Autodesk Fusion 360 part; units mm, degrees
(part 4 of 4)
  spline S141 degree 3 poles (-72.7265, -168.4304) (-72.7884, -168.2804) (-72.9148, -167.9746) (-72.9308, -167.6439) (-72.9389, -167.4754) knots 0 0 0 0 0.048305 0.098484 0.098484 0.098484 0.098484
  spline S142 degree 3 poles (-72.9389, -167.4754) (-72.9169, -167.1911) (-72.8736, -166.6318) (-72.5364, -166.1842) (-72.3707, -165.9642) knots 0 0 0 0 0.083642 0.164485 0.164485 0.164485 0.164485
  spline S143 degree 3 poles (-72.3707, -165.9642) (-72.1132, -165.7849) (-71.5025, -165.3598) (-70.7517, -165.351) (-70.3175, -165.3458) knots 0 0 0 0 0.092246 0.218774 0.218774 0.218774 0.218774
  line L141 (-70.3175, -165.3458) -> (-68.5222, -165.3458)
  spline S144 degree 3 poles (-60.5385, -163.7916) (-60.4695, -163.7159) (-60.3365, -163.5701) (-60.2279, -163.4053) (-60.1756, -163.3261) knots 0 0 0 0 0.03068 0.059109 0.059109 0.059109 0.059109
  line L142 (-60.1756, -163.3261) -> (-63.6088, -163.3261)
  line L143 (-63.6088, -163.3261) -> (-63.6088, -162.5)
  line L144 (-63.6088, -162.5) -> (-58.9819, -162.5)
  spline S145 degree 3 poles (-58.9819, -162.5) (-58.9837, -162.6023) (-58.9871, -162.8063) (-59.0506, -163.0002) (-59.0822, -163.0969) knots 0 0 0 0 0.030508 0.060828 0.060828 0.060828 0.060828
  spline S146 degree 3 poles (-59.0822, -163.0969) (-59.1526, -163.257) (-59.3001, -163.5921) (-59.5286, -163.8784) (-59.648, -164.028) knots 0 0 0 0 0.052239 0.109365 0.109365 0.109365 0.109365
  spline S147 degree 3 poles (-59.648, -164.028) (-59.8035, -164.1959) (-60.1542, -164.5746) (-60.5514, -164.9044) (-60.7725, -165.088) knots 0 0 0 0 0.068595 0.154681 0.154681 0.154681 0.154681
  spline S148 degree 3 poles (-60.7725, -165.088) (-61.1011, -165.3574) (-61.6548, -165.8114) (-62.1241, -166.3512) (-62.3148, -166.5706) knots 0 0 0 0 0.127181 0.214261 0.214261 0.214261 0.214261
  spline S149 degree 3 poles (-62.3148, -166.5706) (-62.4315, -166.7418) (-62.646, -167.0563) (-62.694, -167.4328) (-62.7159, -167.6044) knots 0 0 0 0 0.061099 0.112287 0.112287 0.112287 0.112287
  spline S150 degree 3 poles (-62.7159, -167.6044) (-62.7008, -167.7679) (-62.6707, -168.0941) (-62.4572, -168.3424) (-62.3506, -168.4662) knots 0 0 0 0 0.04797 0.095708 0.095708 0.095708 0.095708
  spline S151 degree 3 poles (-62.3506, -168.4662) (-62.2159, -168.5685) (-61.9348, -168.782) (-61.5818, -168.8051) (-61.398, -168.8172) knots 0 0 0 0 0.049633 0.103533 0.103533 0.103533 0.103533
  spline S152 degree 3 poles (-61.398, -168.8172) (-61.2046, -168.8047) (-60.8349, -168.7809) (-60.5437, -168.5533) (-60.4048, -168.4447) knots 0 0 0 0 0.056637 0.108292 0.108292 0.108292 0.108292
  spline S153 degree 3 poles (-60.4048, -168.4447) (-60.2961, -168.3025) (-60.0641, -167.9991) (-60.0403, -167.6166) (-60.0276, -167.4134) knots 0 0 0 0 0.052525 0.112047 0.112047 0.112047 0.112047
  line L145 (-60.0276, -167.4134) -> (-59.1443, -167.5041)
  spline S154 degree 3 poles (-59.1443, -167.5041) (-59.1884, -167.8075) (-59.2712, -168.3775) (-59.6499, -168.8088) (-59.8271, -169.0106) knots 0 0 0 0 0.089723 0.168584 0.168584 0.168584 0.168584
  spline S155 degree 3 poles (-59.8271, -169.0106) (-60.051, -169.1615) (-60.53, -169.4844) (-61.1089, -169.5133) (-61.4171, -169.5286) knots 0 0 0 0 0.079498 0.170078 0.170078 0.170078 0.170078
  spline S156 degree 3 poles (-61.4171, -169.5286) (-61.7286, -169.5115) (-62.3162, -169.4792) (-62.7896, -169.1328) (-63.0119, -168.97) knots 0 0 0 0 0.09132 0.172247 0.172247 0.172247 0.172247
  spline S157 degree 3 poles (-63.0119, -168.97) (-63.1832, -168.7719) (-63.5277, -168.3736) (-63.5753, -167.849) (-63.5993, -167.5853) knots 0 0 0 0 0.076505 0.153832 0.153832 0.153832 0.153832
  spline S158 degree 3 poles (-63.5993, -167.5853) (-63.5917, -167.445) (-63.5765, -167.1609) (-63.4775, -166.8942) (-63.4274, -166.7592) knots 0 0 0 0 0.041882 0.084809 0.084809 0.084809 0.084809
  spline S159 degree 3 poles (-63.4274, -166.7592) (-63.3561, -166.6171) (-63.2014, -166.3088) (-62.9775, -166.0461) (-62.8567, -165.9045) knots 0 0 0 0 0.04752 0.103099 0.103099 0.103099 0.103099
  spline S160 degree 3 poles (-62.8567, -165.9045) (-62.6822, -165.7246) (-62.2618, -165.2912) (-61.8011, -164.9009) (-61.5317, -164.6726) knots 0 0 0 0 0.075166 0.181017 0.181017 0.181017 0.181017
  spline S161 degree 3 poles (-61.5317, -164.6726) (-61.3174, -164.4938) (-60.9774, -164.2102) (-60.657, -163.9046) (-60.5385, -163.7916) knots 0 0 0 0 0.083681 0.13279 0.13279 0.13279 0.13279
  spline S162 degree 3 poles (-51.1801, -13.3847) (-51.3211, -13.3941) (-51.5954, -13.4125) (-51.8227, -13.5664) (-51.9332, -13.6412) knots 0 0 0 0 0.041561 0.080838 0.080838 0.080838 0.080838
  spline S163 degree 3 poles (-51.9332, -13.6412) (-52.0286, -13.7421) (-52.2336, -13.9588) (-52.3099, -14.248) (-52.3506, -14.4025) knots 0 0 0 0 0.041026 0.088063 0.088063 0.088063 0.088063
  line L146 (-52.3506, -14.4025) -> (-52.8799, -14.2688)
  spline S164 degree 3 poles (-52.8799, -14.2688) (-52.8176, -14.0678) (-52.6993, -13.6863) (-52.4154, -13.4066) (-52.281, -13.2742) knots 0 0 0 0 0.062011 0.117707 0.117707 0.117707 0.117707
  spline S165 degree 3 poles (-52.281, -13.2742) (-52.1256, -13.1744) (-51.8037, -12.9677) (-51.4214, -12.944) (-51.2237, -12.9318) knots 0 0 0 0 0.054488 0.112794 0.112794 0.112794 0.112794
  spline S166 degree 3 poles (-51.2237, -12.9318) (-51.0244, -12.939) (-50.6543, -12.9523) (-50.3242, -13.1184) (-50.1719, -13.1951) knots 0 0 0 0 0.058997 0.109568 0.109568 0.109568 0.109568
  spline S167 degree 3 poles (-50.1719, -13.1951) (-50.0439, -13.2951) (-49.7798, -13.5015) (-49.6316, -13.8026) (-49.5553, -13.9577) knots 0 0 0 0 0.048078 0.099208 0.099208 0.099208 0.099208
  spline S168 degree 3 poles (-49.5553, -13.9577) (-49.4936, -14.1285) (-49.3685, -14.4751) (-49.3521, -14.8433) (-49.3438, -15.03) knots 0 0 0 0 0.054148 0.109857 0.109857 0.109857 0.109857
  spline S169 degree 3 poles (-49.3438, -15.03) (-49.3518, -15.2277) (-49.367, -15.6055) (-49.5129, -15.9539) (-49.5825, -16.1201) knots 0 0 0 0 0.058796 0.112388 0.112388 0.112388 0.112388
  spline S170 degree 3 poles (-49.5825, -16.1201) (-49.6697, -16.2654) (-49.8423, -16.5529) (-50.1231, -16.7361) (-50.2619, -16.8267) knots 0 0 0 0 0.050116 0.099176 0.099176 0.099176 0.099176
  spline S171 degree 3 poles (-50.2619, -16.8267) (-50.4137, -16.8972) (-50.7214, -17.04) (-51.0602, -17.0587) (-51.2319, -17.0682) knots 0 0 0 0 0.049699 0.100774 0.100774 0.100774 0.100774
  spline S172 degree 3 poles (-51.2319, -17.0682) (-51.4208, -17.0578) (-51.7828, -17.038) (-52.0931, -16.8517) (-52.2415, -16.7626) knots 0 0 0 0 0.055778 0.106905 0.106905 0.106905 0.106905
  spline S173 degree 3 poles (-52.2415, -16.7626) (-52.3684, -16.6475) (-52.6307, -16.4096) (-52.7501, -16.0756) (-52.8117, -15.9031) knots 0 0 0 0 0.05057 0.104573 0.104573 0.104573 0.104573
  line L147 (-52.8117, -15.9031) -> (-52.2906, -15.7804)
  spline S174 degree 3 poles (-52.2906, -15.7804) (-52.2434, -15.9124) (-52.1566, -16.1556) (-51.9714, -16.3344) (-51.8868, -16.4161) knots 0 0 0 0 0.041397 0.07622 0.07622 0.07622 0.07622
  spline S175 degree 3 poles (-51.8868, -16.4161) (-51.7897, -16.4742) (-51.5851, -16.5966) (-51.3465, -16.6088) (-51.221, -16.6153) knots 0 0 0 0 0.033404 0.070439 0.070439 0.070439 0.070439
  spline S176 degree 3 poles (-51.221, -16.6153) (-51.0766, -16.6081) (-50.8019, -16.5945) (-50.5633, -16.4587) (-50.4502, -16.3943) knots 0 0 0 0 0.042685 0.08119 0.08119 0.08119 0.08119
  spline S177 degree 3 poles (-50.4502, -16.3943) (-50.3545, -16.3138) (-50.1613, -16.1513) (-50.0641, -15.9183) (-50.015, -15.8008) knots 0 0 0 0 0.036948 0.074549 0.074549 0.074549 0.074549
  spline S178 degree 3 poles (-50.015, -15.8008) (-49.9784, -15.6756) (-49.9051, -15.4247) (-49.8947, -15.1635) (-49.8895, -15.0327) knots 0 0 0 0 0.038978 0.078087 0.078087 0.078087 0.078087
  spline S179 degree 3 poles (-49.8895, -15.0327) (-49.8942, -14.8721) (-49.903, -14.5682) (-49.9949, -14.2785) (-50.0382, -14.1419) knots 0 0 0 0 0.047928 0.09071 0.09071 0.09071 0.09071
  spline S180 degree 3 poles (-50.0382, -14.1419) (-50.093, -14.024) (-50.1994, -13.7952) (-50.4023, -13.6456) (-50.5007, -13.573) knots 0 0 0 0 0.038298 0.074371 0.074371 0.074371 0.074371
  spline S181 degree 3 poles (-50.5007, -13.573) (-50.6074, -13.5181) (-50.8209, -13.4083) (-51.0604, -13.3926) (-51.1801, -13.3847) knots 0 0 0 0 0.035595 0.071173 0.071173 0.071173 0.071173
  line L148 (-58.3806, -16.1432) -> (-58.3806, -13)
  line L149 (-58.3806, -13) -> (-57.8731, -13)
  line L150 (-57.8731, -13) -> (-57.8731, -17)
  line L151 (-57.8731, -17) -> (-58.4161, -17)
  line L152 (-58.4161, -17) -> (-60.5171, -13.8595)
  line L153 (-60.5171, -13.8595) -> (-60.5171, -17)
  line L154 (-60.5171, -17) -> (-61.0246, -17)
  line L155 (-61.0246, -17) -> (-61.0246, -13)
  line L156 (-61.0246, -13) -> (-60.4816, -13)
  line L157 (-60.4816, -13) -> (-58.3806, -16.1432)
  line L158 (-65.8649, -14.7763) -> (-65.8649, -13)
  line L159 (-65.8649, -13) -> (-65.3356, -13)
  line L160 (-65.3356, -13) -> (-65.3356, -17)
  line L161 (-65.3356, -17) -> (-67.1091, -17)
  spline S182 degree 3 poles (-67.1091, -17) (-67.2672, -16.9988) (-67.5431, -16.9967) (-67.8087, -16.9235) (-67.9222, -16.8922) knots 0 0 0 0 0.047144 0.082328 0.082328 0.082328 0.082328
  spline S183 degree 3 poles (-67.9222, -16.8922) (-68.0108, -16.8486) (-68.1914, -16.7597) (-68.3077, -16.5953) (-68.367, -16.5116) knots 0 0 0 0 0.029135 0.059372 0.059372 0.059372 0.059372
  spline S184 degree 3 poles (-68.367, -16.5116) (-68.4155, -16.4178) (-68.5135, -16.2286) (-68.5267, -16.0159) (-68.5334, -15.9086) knots 0 0 0 0 0.031313 0.063169 0.063169 0.063169 0.063169
  spline S185 degree 3 poles (-68.5334, -15.9086) (-68.5227, -15.7731) (-68.5016, -15.5065) (-68.3382, -15.295) (-68.2578, -15.191) knots 0 0 0 0 0.039823 0.07837 0.07837 0.07837 0.07837
  spline S186 degree 3 poles (-68.2578, -15.191) (-68.1454, -15.1016) (-67.8958, -14.9032) (-67.5801, -14.8494) (-67.4066, -14.8199) knots 0 0 0 0 0.042418 0.094205 0.094205 0.094205 0.094205
  spline S187 degree 3 poles (-67.4066, -14.8199) (-67.4696, -14.7888) (-67.5827, -14.7329) (-67.6819, -14.6551) (-67.7258, -14.6207) knots 0 0 0 0 0.02103 0.037715 0.037715 0.037715 0.037715
  spline S188 degree 3 poles (-67.7258, -14.6207) (-67.8036, -14.543) (-67.967, -14.3798) (-68.097, -14.1888) (-68.1651, -14.0887) knots 0 0 0 0 0.032909 0.069134 0.069134 0.069134 0.069134
  line L162 (-68.1651, -14.0887) -> (-68.8608, -13)
  line L163 (-68.8608, -13) -> (-68.1951, -13)
  line L164 (-68.1951, -13) -> (-67.6658, -13.8322)
  spline S189 degree 3 poles (-67.6658, -13.8322) (-67.5966, -13.9391) (-67.4751, -14.1268) (-67.3414, -14.3061) (-67.2838, -14.3834) knots 0 0 0 0 0.038178 0.067075 0.067075 0.067075 0.067075
  spline S190 degree 3 poles (-67.2838, -14.3834) (-67.2386, -14.4398) (-67.1591, -14.5392) (-67.0585, -14.6171) (-67.015, -14.6508) knots 0 0 0 0 0.021583 0.038029 0.038029 0.038029 0.038029
  spline S191 degree 3 poles (-67.015, -14.6508) (-66.9759, -14.6741) (-66.8998, -14.7196) (-66.8148, -14.7449) (-66.7735, -14.7572) knots 0 0 0 0 0.013612 0.02648 0.02648 0.02648 0.02648
  spline S192 degree 3 poles (-66.7735, -14.7572) (-66.734, -14.7627) (-66.6363, -14.7763) (-66.5376, -14.7763) (-66.4789, -14.7763) knots 0 0 0 0 0.011955 0.02956 0.02956 0.02956 0.02956
  line L165 (-66.4789, -14.7763) -> (-65.8649, -14.7763)
  spline S193 degree 3 poles (-70.105, -13.2046) (-69.9657, -13.304) (-69.6867, -13.503) (-69.5164, -13.8005) (-69.4311, -13.9495) knots 0 0 0 0 0.050683 0.101518 0.101518 0.101518 0.101518
  spline S194 degree 3 poles (-69.4311, -13.9495) (-69.3643, -14.1092) (-69.2304, -14.4289) (-69.2114, -14.775) (-69.2019, -14.9482) knots 0 0 0 0 0.05152 0.103135 0.103135 0.103135 0.103135
  spline S195 degree 3 poles (-69.2019, -14.9482) (-69.2174, -15.2545) (-69.2463, -15.8278) (-69.5809, -16.2916) (-69.7367, -16.5075) knots 0 0 0 0 0.08978 0.168002 0.168002 0.168002 0.168002
  spline S196 degree 3 poles (-69.7367, -16.5075) (-69.9312, -16.6718) (-70.3297, -17.0085) (-70.8506, -17.0498) (-71.1173, -17.0709) knots 0 0 0 0 0.074417 0.152506 0.152506 0.152506 0.152506
  spline S197 degree 3 poles (-71.1173, -17.0709) (-71.296, -17.0607) (-71.6471, -17.0407) (-71.9616, -16.8835) (-72.116, -16.8063) knots 0 0 0 0 0.053074 0.104281 0.104281 0.104281 0.104281
  spline S198 degree 3 poles (-72.116, -16.8063) (-72.2556, -16.7089) (-72.5363, -16.5133) (-72.7078, -16.2171) (-72.794, -16.0682) knots 0 0 0 0 0.050395 0.101317 0.101317 0.101317 0.101317
  spline S199 degree 3 poles (-72.794, -16.0682) (-72.862, -15.902) (-73.0028, -15.558) (-73.0189, -15.1865) (-73.0273, -14.9945) knots 0 0 0 0 0.053456 0.11061 0.11061 0.11061 0.11061
  spline S200 degree 3 poles (-73.0273, -14.9945) (-73.0184, -14.7998) (-73.0012, -14.422) (-72.8533, -14.0743) (-72.7817, -13.9059) knots 0 0 0 0 0.057966 0.112404 0.112404 0.112404 0.112404
  spline S201 degree 3 poles (-72.7817, -13.9059) (-72.6923, -13.7561) (-72.5159, -13.4604) (-72.228, -13.2718) (-72.0859, -13.1787) knots 0 0 0 0 0.051579 0.10182 0.10182 0.10182 0.10182
  spline S202 degree 3 poles (-72.0859, -13.1787) (-71.9326, -13.1067) (-71.6247, -12.9621) (-71.2851, -12.9419) (-71.1146, -12.9318) knots 0 0 0 0 0.050325 0.101043 0.101043 0.101043 0.101043
  spline S203 degree 3 poles (-71.1146, -12.9318) (-70.933, -12.9422) (-70.5771, -12.9625) (-70.2602, -13.1251) (-70.105, -13.2046) knots 0 0 0 0 0.053912 0.105611 0.105611 0.105611 0.105611
  spline S204 degree 3 poles (-80.5389, -13.6739) (-80.6107, -13.8001) (-80.7884, -14.1127) (-80.7876, -14.4754) (-80.7872, -14.6917) knots 0 0 0 0 0.042926 0.106327 0.106327 0.106327 0.106327
  line L166 (-80.7872, -14.6917) -> (-80.7872, -17)
  line L167 (-80.7872, -17) -> (-81.3165, -17)
  line L168 (-81.3165, -17) -> (-81.3165, -14.6889)
  spline S205 degree 3 poles (-81.3165, -14.6889) (-81.314, -14.5073) (-81.3095, -14.1818) (-81.2197, -13.8693) (-81.1801, -13.7312) knots 0 0 0 0 0.0542 0.097116 0.097116 0.097116 0.097116
  spline S206 degree 3 poles (-81.1801, -13.7312) (-81.1239, -13.6176) (-81.0085, -13.384) (-80.7965, -13.2321) (-80.6876, -13.1542) knots 0 0 0 0 0.037423 0.076915 0.076915 0.076915 0.076915
  spline S207 degree 3 poles (-80.6876, -13.1542) (-80.5527, -13.0894) (-80.258, -12.948) (-79.9306, -12.9375) (-79.7531, -12.9318) knots 0 0 0 0 0.044416 0.096997 0.096997 0.096997 0.096997
  spline S208 degree 3 poles (-79.7531, -12.9318) (-79.5803, -12.9368) (-79.2615, -12.946) (-78.968, -13.0691) (-78.8336, -13.1255) knots 0 0 0 0 0.05132 0.094686 0.094686 0.094686 0.094686
  spline S209 degree 3 poles (-78.8336, -13.1255) (-78.7231, -13.1969) (-78.5035, -13.3389) (-78.3832, -13.5709) (-78.3233, -13.6862) knots 0 0 0 0 0.038729 0.076986 0.076986 0.076986 0.076986
  spline S210 degree 3 poles (-78.3233, -13.6862) (-78.2789, -13.8299) (-78.1782, -14.156) (-78.1733, -14.4978) (-78.1705, -14.6889) knots 0 0 0 0 0.044904 0.101888 0.101888 0.101888 0.101888
  line L169 (-78.1705, -14.6889) -> (-78.1705, -17)
  line L170 (-78.1705, -17) -> (-78.6999, -17)
  line L171 (-78.6999, -17) -> (-78.6999, -14.6917)
  spline S211 degree 3 poles (-78.6999, -14.6917) (-78.7004, -14.5398) (-78.7013, -14.2793) (-78.7687, -14.0282) (-78.7967, -13.9236) knots 0 0 0 0 0.045324 0.077698 0.077698 0.077698 0.077698
  spline S212 degree 3 poles (-78.7967, -13.9236) (-78.8351, -13.8459) (-78.9122, -13.6895) (-79.0568, -13.592) (-79.1296, -13.543) knots 0 0 0 0 0.02552 0.051354 0.051354 0.051354 0.051354
  spline S213 degree 3 poles (-79.1296, -13.543) (-79.2157, -13.504) (-79.3989, -13.4211) (-79.6001, -13.4134) (-79.7067, -13.4093) knots 0 0 0 0 0.028079 0.059737 0.059737 0.059737 0.059737
  spline S214 degree 3 poles (-79.7067, -13.4093) (-79.8797, -13.4132) (-80.1854, -13.4201) (-80.4319, -13.5971) (-80.5389, -13.6739) knots 0 0 0 0 0.050436 0.089135 0.089135 0.089135 0.089135
  line L172 (-86.8527, -17) -> (-86.8527, -13)
  line L173 (-86.8527, -13) -> (-86.3233, -13)
  line L174 (-86.3233, -13) -> (-86.3233, -17)
  line L175 (-86.3233, -17) -> (-86.8527, -17)
  line L176 (-82.6999, -16.1432) -> (-82.6999, -13)
  line L177 (-82.6999, -13) -> (-82.1924, -13)
  line L178 (-82.1924, -13) -> (-82.1924, -17)
  line L179 (-82.1924, -17) -> (-82.7353, -17)
  line L180 (-82.7353, -17) -> (-84.8363, -13.8595)
  line L181 (-84.8363, -13.8595) -> (-84.8363, -17)
  line L182 (-84.8363, -17) -> (-85.3438, -17)
  line L183 (-85.3438, -17) -> (-85.3438, -13)
  line L184 (-85.3438, -13) -> (-84.8008, -13)
  line L185 (-84.8008, -13) -> (-82.6999, -16.1432)
  line L186 (-76.1869, -13.472) -> (-76.1869, -13)
  line L187 (-76.1869, -13) -> (-73.6876, -13)
  line L188 (-73.6876, -13) -> (-73.6876, -17)
  line L189 (-73.6876, -17) -> (-74.2169, -17)
  line L190 (-74.2169, -17) -> (-74.2169, -13.472)
  line L191 (-74.2169, -13.472) -> (-76.1869, -13.472)
  line L192 (-89.3329, -16.528) -> (-89.3329, -13)
  line L193 (-89.3329, -13) -> (-88.8036, -13)
  line L194 (-88.8036, -13) -> (-88.8036, -16.528)
  line L195 (-88.8036, -16.528) -> (-87.4857, -16.528)
  line L196 (-87.4857, -16.528) -> (-87.4857, -17)
  line L197 (-87.4857, -17) -> (-90.6562, -17)
  line L198 (-90.6562, -17) -> (-90.6562, -16.528)
  line L199 (-90.6562, -16.528) -> (-89.3329, -16.528)
  line L200 (-63.4611, -16.528) -> (-63.4611, -13)
  line L201 (-63.4611, -13) -> (-62.9318, -13)
  line L202 (-62.9318, -13) -> (-62.9318, -16.528)
  line L203 (-62.9318, -16.528) -> (-61.6139, -16.528)
  line L204 (-61.6139, -16.528) -> (-61.6139, -17)
  line L205 (-61.6139, -17) -> (-64.7844, -17)
  line L206 (-64.7844, -17) -> (-64.7844, -16.528)
  line L207 (-64.7844, -16.528) -> (-63.4611, -16.528)
  spline S215 degree 3 poles (-54.2742, -13.2046) (-54.1349, -13.304) (-53.8558, -13.503) (-53.6855, -13.8005) (-53.6003, -13.9495) knots 0 0 0 0 0.050683 0.101518 0.101518 0.101518 0.101518
  spline S216 degree 3 poles (-53.6003, -13.9495) (-53.5334, -14.1092) (-53.3996, -14.4289) (-53.3806, -14.775) (-53.3711, -14.9482) knots 0 0 0 0 0.05152 0.103135 0.103135 0.103135 0.103135
  spline S217 degree 3 poles (-53.3711, -14.9482) (-53.3865, -15.2545) (-53.4155, -15.8278) (-53.7501, -16.2916) (-53.9059, -16.5075) knots 0 0 0 0 0.08978 0.168002 0.168002 0.168002 0.168002
  spline S218 degree 3 poles (-53.9059, -16.5075) (-54.1003, -16.6718) (-54.4989, -17.0085) (-55.0198, -17.0498) (-55.2865, -17.0709) knots 0 0 0 0 0.074417 0.152506 0.152506 0.152506 0.152506
  spline S219 degree 3 poles (-55.2865, -17.0709) (-55.4652, -17.0607) (-55.8163, -17.0407) (-56.1307, -16.8835) (-56.2851, -16.8063) knots 0 0 0 0 0.053074 0.104281 0.104281 0.104281 0.104281
  spline S220 degree 3 poles (-56.2851, -16.8063) (-56.4248, -16.7089) (-56.7055, -16.5133) (-56.877, -16.2171) (-56.9632, -16.0682) knots 0 0 0 0 0.050395 0.101317 0.101317 0.101317 0.101317
  spline S221 degree 3 poles (-56.9632, -16.0682) (-57.0312, -15.902) (-57.1719, -15.558) (-57.1881, -15.1865) (-57.1965, -14.9945) knots 0 0 0 0 0.053456 0.11061 0.11061 0.11061 0.11061
  spline S222 degree 3 poles (-57.1965, -14.9945) (-57.1876, -14.7998) (-57.1703, -14.422) (-57.0225, -14.0743) (-56.9509, -13.9059) knots 0 0 0 0 0.057966 0.112404 0.112404 0.112404 0.112404
  spline S223 degree 3 poles (-56.9509, -13.9059) (-56.8615, -13.7561) (-56.6851, -13.4604) (-56.3972, -13.2718) (-56.2551, -13.1787) knots 0 0 0 0 0.051579 0.10182 0.10182 0.10182 0.10182
  spline S224 degree 3 poles (-56.2551, -13.1787) (-56.1018, -13.1067) (-55.7938, -12.9621) (-55.4542, -12.9419) (-55.2838, -12.9318) knots 0 0 0 0 0.050325 0.101044 0.101044 0.101044 0.101044
  spline S225 degree 3 poles (-55.2838, -12.9318) (-55.1021, -12.9422) (-54.7463, -12.9625) (-54.4294, -13.1251) (-54.2742, -13.2046) knots 0 0 0 0 0.053912 0.105611 0.105611 0.105611 0.105611
  line L208 (-119, -106) -> (-119, -146)
  line L209 (0, -174) -> (0, -6)
  line L210 (-70, -180) -> (-70, -154.9511)
  line L211 (-119, -146) -> (-70, -146)
  line L212 (-119, -106) -> (-70, -106)
  line L213 (-21, -146) -> (-70, -146)
  line L214 (-21, -106) -> (-21, -146)
  line L215 (-21, -106) -> (-70, -106)
  dimension "d1004" = 180
  dimension "d1005" = 140
  dimension "d1007" = 21
  dimension "d1008" = 34
  dimension "d1009" = 49
  dimension "d1011" = 49
  constraint midpoint L115 L210.start
  constraint perpendicular L138 L210
  constraint perpendicular L208 L211
  constraint perpendicular L208 L212
  constraint symmetric L208.end L210 L213.start
  constraint symmetric L208.start L210 L214.start
  constraint symmetric L210 L211.end L213.end
  constraint symmetric L210 L212.end L215.end
  measures "d1004" distance of L113 L115
  measures "d1005" distance of L114 L209
  measures "d1007" distance of L114 L208
  measures "d1008" distance of L115 L208.end
  measures "d1009" distance of L208.end L211.end
  measures "d1011" distance of L208.start L212.end
extrude "Extrude45'" cut sketch "Sketch6" against normal blind 20 contours L208 L211 L212 L213 L214 L215 bodies 2 in component "02 LID - LCD buttons LEDs"
sketch "Sketch7" plane through (0, 0, 69.5) normal (0, 0, 1) x (-1, 0, 0)
  line L0 (-77.22, -63.2) -> (-78.02, -63.2)
  line L1 (-78.02, -63.2) -> (-78.02, -60)
  line L2 (-78.02, -60) -> (-77.22, -60)
  line L3 (-77.22, -60) -> (-77.22, -63.2)
  line L4 (-70.4, -63.2) -> (-71.2, -63.2)
  line L5 (-71.2, -63.2) -> (-71.2, -60)
  line L6 (-71.2, -60) -> (-70.4, -60)
  line L7 (-70.4, -60) -> (-70.4, -63.2)
  line L8 (-61.98, -63.2) -> (-62.78, -63.2)
  line L9 (-62.78, -63.2) -> (-62.78, -60)
  line L10 (-62.78, -60) -> (-61.98, -60)
  line L11 (-61.98, -60) -> (-61.98, -63.2)
  circle A0 centre (-62.38, -53) radius 3.15
  circle A1 centre (-70, -53) radius 3.15
  circle A2 centre (-77.62, -53) radius 3.15
  arc A3 (-38, -26) -> (-42, -22) centre (-42, -26) ccw
  line L12 (-42, -22) -> (-98, -22)
  arc A4 (-98, -22) -> (-102, -26) centre (-98, -26) ccw
  line L13 (-102, -26) -> (-102, -68)
  arc A5 (-102, -68) -> (-98, -72) centre (-98, -68) ccw
  line L14 (-98, -72) -> (-42, -72)
  arc A6 (-42, -72) -> (-38, -68) centre (-42, -68) ccw
  line L15 (-38, -68) -> (-38, -26)
  line L16 (-59, -37) -> (-59, -41)
  arc A7 (-61, -43) -> (-59, -41) centre (-61, -41) ccw
  line L17 (-61, -43) -> (-79, -43)
  arc A8 (-81, -41) -> (-79, -43) centre (-79, -41) ccw
  line L18 (-81, -41) -> (-81, -37)
  arc A9 (-79, -35) -> (-81, -37) centre (-79, -37) ccw
  line L19 (-79, -35) -> (-61, -35)
  arc A10 (-59, -37) -> (-61, -35) centre (-61, -37) ccw
  circle A11 centre (-97, -62) radius 1.8
  circle A12 centre (-43, -32) radius 1.8
  circle A13 centre (-97, -32) radius 1.8
  circle A14 centre (-43, -62) radius 1.8
  line L20 (-68.8, -63.2) -> (-69.6, -63.2)
  line L21 (-69.6, -63.2) -> (-69.6, -60)
  line L22 (-69.6, -60) -> (-68.8, -60)
  line L23 (-68.8, -60) -> (-68.8, -63.2)
  line L24 (-75.62, -63.2) -> (-76.42, -63.2)
  line L25 (-76.42, -63.2) -> (-76.42, -60)
  line L26 (-76.42, -60) -> (-75.62, -60)
  line L27 (-75.62, -60) -> (-75.62, -63.2)
  line L28 (-78.82, -63.2) -> (-79.62, -63.2)
  line L29 (-79.62, -63.2) -> (-79.62, -60)
  line L30 (-79.62, -60) -> (-78.82, -60)
  line L31 (-78.82, -60) -> (-78.82, -63.2)
  line L32 (-63, -51.5) -> (-76.5, -51.5)
  arc A15 (-76.5, -51.5) -> (-76.5, -55) centre (-76.5, -53.25) ccw
  line L33 (-76.5, -55) -> (-63, -55)
  arc A16 (-63, -55) -> (-63, -51.5) centre (-63, -53.25) ccw
  line L34 (-63, -53.25) -> (-76.5, -53.25) construction
  dimension "d1014" = 13.5
  dimension "d1015" = 3.5
  dimension "d1016" = 17
  dimension "d1017" = 50
  dimension "d1018" = 25
  constraint tangent L32 A15
  constraint tangent A15 L33
  constraint parallel L32 L33
  constraint tangent L33 A16
  constraint tangent L32 A16
  constraint horizontal L34
  measures "d1014" distance of A16.centre A15.centre
  measures "d1015" diameter of A15
  measures "d1016" distance of L14 L33
  measures "d1017" distance of L12 L14
  measures "d1018" distance of L15 A16.centre
extrude "Extrude18" add sketch "Sketch7" against normal blind 2.5 contours A0 L32 L33 A16 | A1 L32 | A1 L33 | A2 L32 A15 L33 picked at (-60.0891, -52.118) picked at (-79.879, -52.5976) bodies 7 in component "V2 removable control fascia"
extrude "Extrude19" cut sketch "Sketch7" against normal blind 2.5 contours A0 A1 L32 L33 | A1 A2 L32 L33 bodies 7 in component "V2 removable control fascia"
extrude "Extrude20" add sketch "Sketch7" against normal blind 2.5 contours L16 A7 L17 A8 L18 A9 L19 A10 bodies 7 in component "V2 removable control fascia"
sketch "Sketch8" plane through (0, 0, 69.5) normal (0, 0, 1) x (-1, 0, 0)
  line L0 (-60.5, -38) -> (-67, -38)
  line L1 (-67, -44.5) -> (-60.5, -44.5)
  line L2 (-60.5, -44.5) -> (-60.5, -38)
  line L3 (-73.5, -44.5) -> (-67, -44.5)
  line L4 (-67, -38) -> (-73.5, -38)
  line L5 (-80, -38) -> (-80, -44.5)
  line L6 (-80, -44.5) -> (-73.5, -44.5)
  line L7 (-73.5, -38) -> (-80, -38)
  line L8 (-63, -51.5) -> (-76.5, -51.5)
  dimension "d1025" = 6.5
  dimension "d1026" = 6.5
  dimension "d1031" = 7
  constraint horizontal L0
  constraint horizontal L1
  constraint vertical L2
  measures "d1025" distance of L0.start L0.end
  measures "d1026" distance of L0.start L1.end
  measures "d1031" distance of L3 L8
extrude "Extrude21" cut sketch "Sketch8" against normal blind 2.5 bodies 7 in component "V2 removable control fascia"
component "01 BASE - PCB at bottom" placed x (1, 0, 0) y (0, 1, 0) z (0, 0, 1) at (0, 0, 0)
component "02 LID - LCD buttons LEDs" placed x (1, 0, 0) y (0, 1, 0) z (0, 0, 1) at (0, 0, 0)
component "V2 MAIN clamp 1" placed x (1, 0, 0) y (0, 1, 0) z (0, 0, 1) at (0, 0, 0)
component "V2 MAIN clamp 2" placed x (1, 0, 0) y (0, 1, 0) z (0, 0, 1) at (0, 0, 0)
component "V2 MAIN clamp 3" placed x (1, 0, 0) y (0, 1, 0) z (0, 0, 1) at (0, 0, 0)
component "V2 MAIN clamp 4" placed x (1, 0, 0) y (0, 1, 0) z (0, 0, 1) at (0, 0, 0)
component "V2 removable control fascia" placed x (1, 0, 0) y (0, 1, 0) z (0, 0, 1) at (0, 0, 0)
component "V2 control PCB removable carrier" placed x (1, 0, 0) y (0, 1, 0) z (0, 0, 1) at (0, 0, 0)
component "REF main board 90x80x20 - photo estimate" placed x (1, 0, 0) y (0, 1, 0) z (0, 0, 1) at (0, 0, 0)
component "REF actual combined buttons LEDs PCB - estimated" placed x (1, 0, 0) y (0, 1, 0) z (0, 0, 1) at (0, 0, 0)
component "V3 RELAY adjustable clamp 1" placed x (1, 0, 0) y (0, 1, 0) z (0, 0, 1) at (0, 0, 0)
component "V3 RELAY adjustable clamp 2" placed x (1, 0, 0) y (0, 1, 0) z (0, 0, 1) at (0, 0, 0)
component "V3 RELAY adjustable clamp 3" placed x (1, 0, 0) y (0, 1, 0) z (0, 0, 1) at (0, 0, 0)
component "V3 RELAY adjustable clamp 4" placed x (1, 0, 0) y (0, 1, 0) z (0, 0, 1) at (0, 0, 0)
component "REF relay envelope 75.5x55x20 - variant not confirmed" placed x (1, 0, 0) y (0, 1, 0) z (0, 0, 1) at (0, 0, 0)
component "REF LCD2004 98x60 - 93x55 mounting - conservative thickness" placed x (1, 0, 0) y (0, 1, 0) z (0, 0, 1) at (0, 0, 0)
equation "button_d = 12.2 mm" comment "ASSUMED: measure actual panel button"
equation "led_d = 5.2 mm" comment "ASSUMED: 5 mm LED clearance"
equation "screw_clearance = 3.4 mm" comment "M3 clearance"
equation "pilot_d = 2.5 mm" comment "Plastic tapping pilot; verify printed fit"
equation "d17 = pilot_d"
equation "d18 = pilot_d"
equation "d19 = pilot_d"
equation "d20 = pilot_d"
equation "d37 = pilot_d"
equation "d38 = pilot_d"
equation "d39 = pilot_d"
equation "d40 = pilot_d"
equation "d53 = screw_clearance"
equation "d54 = screw_clearance"
equation "d55 = screw_clearance"
equation "d56 = screw_clearance"
equation "d73 = pilot_d"
equation "d74 = pilot_d"
equation "d75 = pilot_d"
equation "d76 = pilot_d"
equation "d81 = button_d"
equation "d82 = button_d"
equation "d83 = button_d"
equation "d88 = led_d"
equation "d89 = led_d"
equation "d90 = led_d"
equation "d96 = 'H2 PRO'"
equation "d102 = 'POWER'"
equation "d108 = 'LOCK'"
equation "d114 = 'PURGE'"
equation "d120 = 'POWER'"
equation "d126 = 'LOCK'"
equation "d132 = 'MODE'"
equation "d408 = 'H2 PRO'"
equation "d414 = 'BRAIN / CONTROL UNIT'"
equation "d420 = 'POWER   LOCK   PURGE'"
equation "d426 = 'STATUS INDICATORS'"
equation "d448 = '1'"
equation "d454 = '2'"
equation "d460 = '3'"
equation "v3_lip_gap = 0.5 mm" comment "PETG removable cover lateral gap each side"
equation "v3_m3_clear = 3.6 mm" comment "M3 clearance for nozzle 0.6"
equation "v3_button_guide = 6.3 mm" comment "Guide for 5.5 mm plunger: 0.4 mm radial clearance"
equation "v3_switch_height = 4.3 mm" comment "Reference B3F-1000 height; actual unmarked switch requires fit check"
equation "v3_relay_w = 75.5 mm" comment "Envelope of documented Addicore variants; not positively identified"
equation "v3_relay_l = 55 mm" comment "Largest documented plan length"
equation "v3_lcd_standoff = 12.8 mm" comment "PCB front to lid underside; conservative 12 mm bezel plus 0.8 gap"
equation "v3_shrink_xy = 0.0030000000000000001" comment "TRIAL ONLY 0.3 percent; applied only by STL export utility, never to CAD"
equation "d713 = v3_m3_clear"
equation "d714 = v3_m3_clear"
equation "d715 = v3_m3_clear"
equation "d716 = v3_m3_clear"
equation "d829 = v3_button_guide"
equation "d830 = v3_button_guide"
equation "d831 = v3_button_guide"
equation "d836 = v3_m3_clear"
equation "d837 = v3_m3_clear"
equation "d838 = v3_m3_clear"
equation "d839 = v3_m3_clear"
equation "d844 = v3_m3_clear"
equation "d845 = v3_m3_clear"
equation "d875 = 'H2 PRO'"
equation "d881 = 'POWER  /  LOCK  /  PURGE'"
equation "d887 = 'CONTROL UNIT'"
named bodies: "BASE_V2_PRINT", "LID_V2_PRINT", "Main PCB", "ESP32 reference", "nRF24 reference", "MPU6050 reference", "Tallest component 20mm total", "Rocker switch side clearance", "SMA connector space", "Control PCB estimated 30x30", "Tactile switch 6x6", "Switch actuator", "Tactile switch 6x6 (1)", "Switch actuator (1)", "Tactile switch 6x6 (2)", "Switch actuator (2)", "LED BLUE", "LED RED", "LED GREEN", "Relay PCB envelope", "SRD relay envelope 1", "SRD relay envelope 2", "SRD relay envelope 3", "SRD relay envelope 4", "Terminal strip envelope", "Control connector reserve", "LCD PCB 98x60", "LCD bezel depth envelope", "LCD viewing area envelope", "LCD I2C backpack reserve", "BASE_V2_PRINT (1)"
